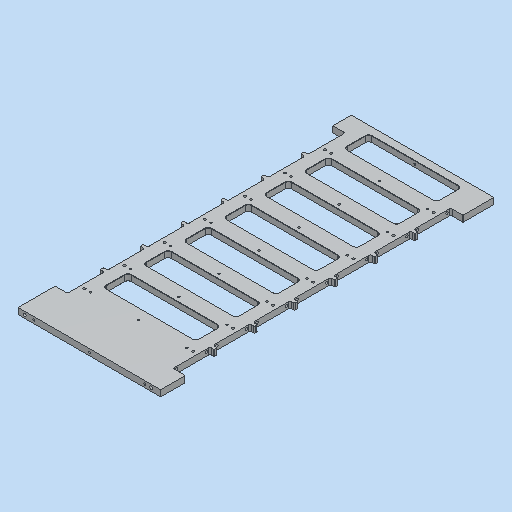
# Autodesk Inventor part: MM0948AN130_G01_114
Saved by Autodesk Inventor 2023.3 (Build 273359000, 359)
## iProperties
Part Number: MM0948AN130_G01_114
Material: 3.3547 AlMg4,5Mn0,7 - AW 5083
Description: =<RBPARTNOTITLE2>
Document SubType Name: Modeling
Designer: ric7an
Mass: 1734.56 g
Surface Area: 1824.37 cm^2
Volume: 642.429 cm^3
Density: 2.7 g/cm^3
Appearance: Aluminium AnP
Created: 2023-03-23
RBDOCUMENTTYPE: DRF
RBDOCUMENTVERSION: 00
RBDRAWINGMAINSCALE: 1:1
RBDRAWINGMISSINGSPEC: --
RBDRAWINGVOLUME: --
RBGBEDGESIN1: +0,5
RBGBEDGESIN2: +0,2
RBGBEDGESOUT1: -0,3
RBGBEDGESOUT2: -0,1
RBMATERIAL: =<Material>
RBMATMEETS: --
RBMATNO: =<Part Number>
RBPARTMADEOF: 10 x 540 x 276 (FM)
RBPARTNO: SIEHE MNR
RBPARTNOTITLE1: manufactured part
RBPARTNOTITLE2: Anfertigungsteil
RBPARTSAFETYINDICATOR: --
RBSURFACE: anodised colourless
RBSURFACE2: eloxiert farblos
RBZEDGESNORM: ISO13715:2002-06
RBZGENDIMCLASS: m
RBZGENDIMNORM: ISO 2768-1:1989-11
RBZGENGEOCLASS: H
RBZGENGEONORM: ISO 2768-2:1989-11
RBZSURFACENORM: ISO13D2:2002-02
RBZTOLERANCENORM: ISO 14405-1:2010-12
AnP_Material: =<Material>
AnP_TemplVers: 20190222
AnP_Kategorie: 1
MaxAbmaße: 10 x 540 x 276 (FM)
AnP_Kommentar_aktuell: =<Comments>
AnP_Material_aktuell: =<Material>
Author: FH/Wi
Keywords: =<RBPARTMADEOF>
Comments: =<RBSURFACE2>
Revision Number: 01
Autodesk Inventor part; units mm, degrees
ref_plane "YZ Plane" through (0, 0, 0) normal (1, 0, 0) x (0, 1, 0)
ref_plane "XZ Plane" through (0, 0, 0) normal (0, 1, 0) x (-1, 0, 0)
sketch "Skizze1" plane through (0, 0, 0) normal (0, 0, 1) x (1, 0, 0)
  line L0 (0, 0) -> (231, 0)
  line L1 (231, 0) -> (231, 540)
  line L2 (231, 540) -> (0, 540)
  line L3 (0, 540) -> (0, 0)
  line L4 (0, 648) -> (0, -108) projected
  line L5 (-46.2, 0) -> (277.2, 0) projected
  point P0 (0, 0)
  dimension "d0" = 540
  dimension "d1" = 231
  constraints: 8 end point, 2 collinear, 2 parallel, 1 horizontal, 1 perpendicular
  measures "d0" distance of L0.end L1.end
  measures "d1" distance of L1.end L2.end
extrude "Extrusion1" add sketch "Skizze1" against normal blind 10
ref_plane "Arbeitsebene1" through (0, 40, -2.5) normal (0, 0, 1) x (1, 0, 0)
sketch "Skizze4" plane through (0, 40, 0) normal (0, 0, 1) x (1, 0, 0)
  line L0 (231, 500) -> (0, 500) projected
  line L1 (0, -40) -> (231, -40) projected
  line L2 (231, -40) -> (231, 500) projected
  point P0 (37.5, 430)
  point P1 (203.5, 430)
  point P2 (193.5, 430)
  point P3 (115.5, 430)
  point P4 (27.5, 430)
  point P5 (115.5, 500)
  dimension "d18" = 78
  dimension "d20" = 10
  dimension "d42" = 10
  dimension "d43" = 156
  dimension "d69" = 470
  dimension "d201" = 27.5
  constraints: 4 horizontal alignment, 1 midpoint, 1 vertical alignment
  measures "d18" distance of point (115.5, 430) point (37.5, 430)
  measures "d20" distance of point (203.5, 430) point (193.5, 430)
  measures "d42" distance of point (37.5, 430) point (27.5, 430)
  measures "d43" distance of point (193.5, 430) point (37.5, 430)
  measures "d69" distance from line of L1 point (27.5, 430)
  measures "d201" distance from line of L2 point (203.5, 430)
hole "Bohrung1" at (37.5, 470, 0) at (193.5, 470, 0) at (115.5, 470, 0) direction (0, 0, -1) diameter 3.242 end through all thread size "M4x0.7" designation "M4" class "6H" standard "ISO Metric profile"
hole "Bohrung2" at (203.5, 470, 0) at (27.5, 470, 0) direction (0, 0, -1) diameter 4 end through all
sketch "Skizze7" plane through (0, 0, 0) normal (0, 0, 1) x (1, 0, 0)
  line L0 (40.5, 527.5) -> (190.5, 527.5)
  line L1 (190.5, 527.5) -> (190.5, 487.5)
  line L2 (190.5, 487.5) -> (40.5, 487.5)
  line L3 (40.5, 487.5) -> (40.5, 527.5)
  line L4 (-48.6, 0) -> (291.6, 0) projected
  line L5 (231, 540) -> (0, 540) projected
  line L6 (40.5, 507.5) -> (190.5, 507.5) construction
  circle A0 centre (203.5, 470) radius 2 projected
  point P0 (0, 0)
  point P1 (115.5, 527.5)
  point P2 (115.5, 540)
  dimension "d60" = 150
  dimension "d61" = 40
  dimension "d163" = 17.5
  constraints: 10 end point, 4 midpoint, 2 parallel, 1 horizontal, 1 perpendicular, 1 vertical alignment
  measures "d60" distance of L0.start L0.end
  measures "d61" distance of L0.end L1.end
  measures "d163" distance from line of A0.centre L2
extrude "Extrusion6" cut sketch "Skizze7" against normal through all contours L0 L1 L2 L3
fillet "Rundung2" radius 5 4 edges at (40.5, 527.5, -5) (40.5, 487.5, -5) (190.5, 487.5, -5) (190.5, 527.5, -5)
sketch "Skizze8" plane through (0, 0, 0) normal (0, -1, 0) x (1, 0, 0)
  line L0 (231, -10) -> (0, -10) projected
  line L1 (0, 0) -> (0, -10) projected
  line L2 (231, 0) -> (231, -10) projected
  line L3 (25.5, -5) -> (205.5, -5)
  point P0 (115.5, -5)
  dimension "d71" = 5
  dimension "d72" = 180
  dimension "d90" = 231
  dimension "d91" = 25.5
  constraints: 2 end point, 1 horizontal, 1 horizontal alignment, 1 midpoint
  measures "d71" distance from line of L0 L3.start
  measures "d72" distance of L3.end L3.start
  measures "d90" distance between parallel lines of L2 L1
  measures "d91" distance from line of L3.start L1
hole "Bohrung3" at (25.5, 0, -5) at (205.5, 0, -5) at (115.5, 0, -5) direction (0, 1, 0) diameter 3.242 depth 15 tip angle 118 thread size "M4x0.7" designation "M4" class "6H" standard "ISO Metric profile"
sketch "Skizze9" plane through (0, 0, 0) normal (0, -1, 0) x (1, 0, 0)
  circle A0 centre (25.5, -5) radius 1.621 projected
  circle A1 centre (205.5, -5) radius 1.621 projected
  point P0 (0, 0)
  point P1 (10.5, -5)
  point P2 (215.5, -5)
  dimension "d92" = 15
  dimension "d187" = 10
  constraints: 2 horizontal alignment
  measures "d92" distance of A0.centre point (10.5, -5)
  measures "d187" distance of point (215.5, -5) A1.centre
hole "Bohrung4" at (10.5, 0, -5) at (215.5, 0, -5) direction (0, 1, 0) diameter 5 depth 10 tip angle 118
sketch "Skizze10" plane through (0, 540, 0) normal (0, 1, 0) x (1, 0, 0)
  line L0 (231, 0) -> (0, 0) projected
  line L1 (231, 0) -> (231, 10) projected
  line L2 (0, 0) -> (0, 10) projected
  line L3 (15.5, 5) -> (215.5, 5)
  point P0 (115.5, 5)
  dimension "d93" = 5
  dimension "d94" = 200
  dimension "d95" = 231
  dimension "d96" = 15.5
  constraints: 2 end point, 1 horizontal, 1 horizontal alignment, 1 midpoint
  measures "d93" distance from line of L0 L3.start
  measures "d94" distance of L3.end L3.start
  measures "d95" distance between parallel lines of L1 L2
  measures "d96" distance from line of L3.start L2
hole "Bohrung5" at (15.5, 540, -5) at (215.5, 540, -5) at (115.5, 540, -5) direction (0, -1, 0) diameter 3.242 depth 15 tip angle 118 thread size "M4x0.7" designation "M4" class "6H" standard "ISO Metric profile"
chamfer "Fase1" distance 0.5 angle 45 16 edges at (40.5, 507.5, -10) (41.9645, 488.9645, -10) (115.5, 487.5, -10) (189.0355, 488.9645, -10) (190.5, 507.5, -10) (189.0355, 526.0355, -10) (115.5, 527.5, -10) (41.9645, 526.0355, -10) (40.5, 507.5, 0) (41.9645, 526.0355, 0) (115.5, 527.5, 0) (189.0355, 526.0355, 0) (190.5, 507.5, 0) (189.0355, 488.9645, 0) (115.5, 487.5, 0) (41.9645, 488.9645, 0)
sketch "Skizze11" plane through (0, 540, 0) normal (0, 1, 0) x (1, 0, 0)
  circle A0 centre (15.5, 5) radius 1.621 projected
  circle A1 centre (215.5, 5) radius 1.621 projected
  point P0 (0, 0)
  point P1 (200.5, 5)
  dimension "d107" = 200
  dimension "d200" = 15
  constraints: 1 horizontal alignment
  measures "d107" distance of A1.centre A0.centre
  measures "d200" distance of A1.centre point (200.5, 5)
hole "Bohrung6" at (200.5, 540, -5) direction (0, -1, 0) diameter 5 depth 10 tip angle 118
sketch "Skizze16" plane through (0, 0, -10) normal (0, 0, -1) x (-1, 0, 0)
  line L0 (0, 0) -> (0, 540) projected
  line L1 (0, 540) -> (-231, 540) projected
  line L2 (0, 510) -> (-20, 510)
  line L3 (-20, 510) -> (-20, 450)
  line L4 (-20, 450) -> (0, 450)
  line L5 (0, 450) -> (0, 510)
  line L6 (-231, 540) -> (-231, 0) projected
  line L7 (-231, 490) -> (-211, 490)
  line L8 (-211, 490) -> (-211, 430)
  line L9 (-211, 430) -> (-231, 430)
  line L10 (-231, 430) -> (-231, 490)
  circle A0 centre (-27.5, 470) radius 2 projected
  circle A1 centre (-203.5, 470) radius 2 projected
  point P0 (0, 450)
  dimension "d148" = 60
  dimension "d149" = 20
  dimension "d150" = 20
  dimension "d164" = 40
  dimension "d165" = 20
  constraints: 16 end point, 5 parallel, 2 horizontal, 2 perpendicular, 2 point on line
  measures "d148" distance of L2.end L3.end
  measures "d149" distance of L3.end L4.end
  measures "d150" distance of L7.start L7.end
  measures "d164" distance from line of L2 A0.centre
  measures "d165" distance from line of A1.centre L7
extrude "Extrusion8" cut sketch "Skizze16" against normal through all contours L4 L3 L2 L0 | L7 L8 L9 L6
sketch "Skizze18" plane through (20, 450, -10) normal (-1, 0, 0) x (0, 0, 1)
  line L0 (10, 60) -> (10, 0) projected
  line L1 (0, 60) -> (10, 60) projected
  line L2 (10, 30) -> (5, 30)
  line L3 (0, 0) -> (0, 60) projected
  point P0 (10, -450)
  point P1 (6, 54)
  point P2 (6, 6)
  dimension "d174" = 6
  dimension "d175" = 6
  constraints: 2 end point, 1 horizontal, 1 midpoint, 1 symmetric about line
  measures "d174" distance from line of point (6, 54) L1
  measures "d175" distance from line of point (6, 54) L3
hole "Bohrung11" at (20, 504, -4) at (20, 456, -4) direction (1, 0, 0) diameter 4.134 depth 14.2 tip angle 118 thread size "M5x0.8" designation "M5" class "6H" standard "ISO Metric profile"
sketch "Skizze20" plane through (211, 430, 1) normal (1, 0, 0) x (0, 0, -1)
  line L0 (10, 30) -> (1, 30)
  line L1 (1, 0) -> (1, 60) projected
  line L2 (1, 60) -> (11, 60) projected
  line L3 (11, 60) -> (11, 0) projected
  point P0 (10, -450)
  point P1 (5, 54)
  point P2 (5, 6)
  dimension "d198" = 6
  dimension "d199" = 6
  constraints: 2 end point, 1 horizontal, 1 midpoint, 1 symmetric about line
  measures "d198" distance from line of point (5, 54) L2
  measures "d199" distance from line of L3 point (5, 54)
hole "Bohrung13" at (211, 484, -4) at (211, 436, -4) direction (-1, 0, 0) diameter 4.134 depth 14.2 tip angle 118
fillet "Rundung4" radius 2.5 4 edges at (20, 450, -5) (20, 510, -5) (211, 490, -5) (211, 430, -5)
pattern_linear "Rechteckige Anordnung2" count 7 spacing 65 along (0, -1, 0) of "Bohrung2", "Bohrung1", "Extrusion8", "Rundung2", "Fase1", "Extrusion6", "Bohrung13", "Bohrung11", "Rundung4"
sketch "Skizze21" plane through (0, 0, 0) normal (0, 0, 1) x (1, 0, 0)
  line L0 (40, 132.5) -> (40, 102.5) projected
  arc A0 (45.5, 138) -> (40, 132.5) centre (45.5, 132.5) ccw projected
  line L1 (185.5, 138) -> (45.5, 138) projected
  arc A1 (191, 132.5) -> (185.5, 138) centre (185.5, 132.5) ccw projected
  line L2 (191, 102.5) -> (191, 132.5) projected
  arc A2 (185.5, 97) -> (191, 102.5) centre (185.5, 102.5) ccw projected
  line L3 (45.5, 97) -> (185.5, 97) projected
  arc A3 (40, 102.5) -> (45.5, 97) centre (45.5, 102.5) ccw projected
  line L4 (40, 262.5) -> (40, 232.5) projected
  arc A4 (45.5, 268) -> (40, 262.5) centre (45.5, 262.5) ccw projected
  line L5 (185.5, 268) -> (45.5, 268) projected
  arc A5 (191, 262.5) -> (185.5, 268) centre (185.5, 262.5) ccw projected
  line L6 (191, 232.5) -> (191, 262.5) projected
  arc A6 (185.5, 227) -> (191, 232.5) centre (185.5, 232.5) ccw projected
  line L7 (45.5, 227) -> (185.5, 227) projected
  arc A7 (40, 232.5) -> (45.5, 227) centre (45.5, 232.5) ccw projected
  line L8 (40, 392.5) -> (40, 362.5) projected
  arc A8 (45.5, 398) -> (40, 392.5) centre (45.5, 392.5) ccw projected
  line L9 (185.5, 398) -> (45.5, 398) projected
  arc A9 (191, 392.5) -> (185.5, 398) centre (185.5, 392.5) ccw projected
  line L10 (191, 362.5) -> (191, 392.5) projected
  arc A10 (185.5, 357) -> (191, 362.5) centre (185.5, 362.5) ccw projected
  line L11 (45.5, 357) -> (185.5, 357) projected
  arc A11 (40, 362.5) -> (45.5, 357) centre (45.5, 362.5) ccw projected
  line L12 (231, 40) -> (213.5, 40) projected
  arc A12 (211, 42.5) -> (213.5, 40) centre (213.5, 42.5) ccw projected
  line L13 (211, 42.5) -> (211, 97.5) projected
  arc A13 (213.5, 100) -> (211, 97.5) centre (213.5, 97.5) ccw projected
  line L14 (213.5, 100) -> (231, 100) projected
  line L15 (231, 100) -> (231, 105) projected
  line L16 (231, 105) -> (213.5, 105) projected
  arc A14 (211, 107.5) -> (213.5, 105) centre (213.5, 107.5) ccw projected
  line L17 (211, 107.5) -> (211, 162.5) projected
  arc A15 (213.5, 165) -> (211, 162.5) centre (213.5, 162.5) ccw projected
  line L18 (213.5, 165) -> (231, 165) projected
  line L19 (231, 165) -> (231, 170) projected
  line L20 (231, 170) -> (213.5, 170) projected
  arc A16 (211, 172.5) -> (213.5, 170) centre (213.5, 172.5) ccw projected
  line L21 (211, 172.5) -> (211, 227.5) projected
  arc A17 (213.5, 230) -> (211, 227.5) centre (213.5, 227.5) ccw projected
  line L22 (213.5, 230) -> (231, 230) projected
  line L23 (231, 230) -> (231, 235) projected
  line L24 (231, 235) -> (213.5, 235) projected
  arc A18 (211, 237.5) -> (213.5, 235) centre (213.5, 237.5) ccw projected
  line L25 (211, 237.5) -> (211, 292.5) projected
  arc A19 (213.5, 295) -> (211, 292.5) centre (213.5, 292.5) ccw projected
  line L26 (213.5, 295) -> (231, 295) projected
  line L27 (231, 295) -> (231, 300) projected
  line L28 (231, 300) -> (213.5, 300) projected
  arc A20 (211, 302.5) -> (213.5, 300) centre (213.5, 302.5) ccw projected
  line L29 (211, 302.5) -> (211, 357.5) projected
  arc A21 (213.5, 360) -> (211, 357.5) centre (213.5, 357.5) ccw projected
  line L30 (213.5, 360) -> (231, 360) projected
  line L31 (231, 360) -> (231, 365) projected
  line L32 (231, 365) -> (213.5, 365) projected
  arc A22 (211, 367.5) -> (213.5, 365) centre (213.5, 367.5) ccw projected
  line L33 (211, 367.5) -> (211, 422.5) projected
  arc A23 (213.5, 425) -> (211, 422.5) centre (213.5, 422.5) ccw projected
  line L34 (213.5, 425) -> (231, 425) projected
  line L35 (231, 425) -> (231, 430) projected
  line L36 (231, 430) -> (213.5, 430) projected
  arc A24 (211, 432.5) -> (213.5, 430) centre (213.5, 432.5) ccw projected
  line L37 (211, 432.5) -> (211, 487.5) projected
  arc A25 (213.5, 490) -> (211, 487.5) centre (213.5, 487.5) ccw projected
  line L38 (213.5, 490) -> (231, 490) projected
  line L39 (231, 490) -> (231, 540) projected
  line L40 (231, 540) -> (0, 540) projected
  line L41 (0, 540) -> (0, 510) projected
  line L42 (0, 510) -> (17.5, 510) projected
  arc A26 (20, 507.5) -> (17.5, 510) centre (17.5, 507.5) ccw projected
  line L43 (20, 507.5) -> (20, 452.5) projected
  arc A27 (17.5, 450) -> (20, 452.5) centre (17.5, 452.5) ccw projected
  line L44 (17.5, 450) -> (0, 450) projected
  line L45 (0, 450) -> (0, 445) projected
  line L46 (0, 445) -> (17.5, 445) projected
  arc A28 (20, 442.5) -> (17.5, 445) centre (17.5, 442.5) ccw projected
  line L47 (20, 442.5) -> (20, 387.5) projected
  arc A29 (17.5, 385) -> (20, 387.5) centre (17.5, 387.5) ccw projected
  line L48 (17.5, 385) -> (0, 385) projected
  line L49 (0, 385) -> (0, 380) projected
  line L50 (0, 380) -> (17.5, 380) projected
  arc A30 (20, 377.5) -> (17.5, 380) centre (17.5, 377.5) ccw projected
  line L51 (20, 377.5) -> (20, 322.5) projected
  arc A31 (17.5, 320) -> (20, 322.5) centre (17.5, 322.5) ccw projected
  line L52 (17.5, 320) -> (0, 320) projected
  line L53 (0, 320) -> (0, 315) projected
  line L54 (0, 315) -> (17.5, 315) projected
  arc A32 (20, 312.5) -> (17.5, 315) centre (17.5, 312.5) ccw projected
  line L55 (20, 312.5) -> (20, 257.5) projected
  arc A33 (17.5, 255) -> (20, 257.5) centre (17.5, 257.5) ccw projected
  line L56 (17.5, 255) -> (0, 255) projected
  line L57 (0, 255) -> (0, 250) projected
  line L58 (0, 250) -> (17.5, 250) projected
  arc A34 (20, 247.5) -> (17.5, 250) centre (17.5, 247.5) ccw projected
  line L59 (20, 247.5) -> (20, 192.5) projected
  arc A35 (17.5, 190) -> (20, 192.5) centre (17.5, 192.5) ccw projected
  line L60 (17.5, 190) -> (0, 190) projected
  line L61 (0, 190) -> (0, 185) projected
  line L62 (0, 185) -> (17.5, 185) projected
  arc A36 (20, 182.5) -> (17.5, 185) centre (17.5, 182.5) ccw projected
  line L63 (20, 182.5) -> (20, 127.5) projected
  arc A37 (17.5, 125) -> (20, 127.5) centre (17.5, 127.5) ccw projected
  line L64 (17.5, 125) -> (0, 125) projected
  line L65 (0, 125) -> (0, 120) projected
  line L66 (0, 120) -> (17.5, 120) projected
  arc A38 (20, 117.5) -> (17.5, 120) centre (17.5, 117.5) ccw projected
  line L67 (20, 117.5) -> (20, 62.5) projected
  arc A39 (17.5, 60) -> (20, 62.5) centre (17.5, 62.5) ccw projected
  line L68 (17.5, 60) -> (0, 60) projected
  line L69 (0, 60) -> (0, 0) projected
  line L70 (0, 0) -> (231, 0) projected
  line L71 (231, 0) -> (231, 40) projected
  circle A40 centre (115.5, 470) radius 1.621 projected
  circle A41 centre (37.5, 470) radius 1.621 projected
  circle A42 centre (193.5, 470) radius 1.621 projected
  circle A43 centre (27.5, 470) radius 2 projected
  circle A44 centre (203.5, 470) radius 2 projected
  line L72 (40, 522.5) -> (40, 492.5) projected
  arc A45 (45.5, 528) -> (40, 522.5) centre (45.5, 522.5) ccw projected
  line L73 (185.5, 528) -> (45.5, 528) projected
  arc A46 (191, 522.5) -> (185.5, 528) centre (185.5, 522.5) ccw projected
  line L74 (191, 492.5) -> (191, 522.5) projected
  arc A47 (185.5, 487) -> (191, 492.5) centre (185.5, 492.5) ccw projected
  line L75 (45.5, 487) -> (185.5, 487) projected
  arc A48 (40, 492.5) -> (45.5, 487) centre (45.5, 492.5) ccw projected
  circle A49 centre (37.5, 405) radius 1.621 projected
  circle A50 centre (115.5, 405) radius 1.621 projected
  circle A51 centre (193.5, 405) radius 1.621 projected
  circle A52 centre (27.5, 405) radius 2 projected
  circle A53 centre (203.5, 405) radius 2 projected
  circle A54 centre (37.5, 340) radius 1.621 projected
  circle A55 centre (115.5, 340) radius 1.621 projected
  circle A56 centre (193.5, 340) radius 1.621 projected
  circle A57 centre (27.5, 340) radius 2 projected
  circle A58 centre (203.5, 340) radius 2 projected
  circle A59 centre (37.5, 275) radius 1.621 projected
  circle A60 centre (115.5, 275) radius 1.621 projected
  circle A61 centre (193.5, 275) radius 1.621 projected
  circle A62 centre (27.5, 275) radius 2 projected
  circle A63 centre (203.5, 275) radius 2 projected
  circle A64 centre (37.5, 210) radius 1.621 projected
  circle A65 centre (115.5, 210) radius 1.621 projected
  circle A66 centre (193.5, 210) radius 1.621 projected
  circle A67 centre (27.5, 210) radius 2 projected
  circle A68 centre (203.5, 210) radius 2 projected
  circle A69 centre (37.5, 145) radius 1.621 projected
  circle A70 centre (115.5, 145) radius 1.621 projected
  circle A71 centre (193.5, 145) radius 1.621 projected
  circle A72 centre (27.5, 145) radius 2 projected
  circle A73 centre (203.5, 145) radius 2 projected
  circle A74 centre (37.5, 80) radius 1.621 projected
  circle A75 centre (115.5, 80) radius 1.621 projected
  circle A76 centre (193.5, 80) radius 1.621 projected
  circle A77 centre (27.5, 80) radius 2 projected
  circle A78 centre (203.5, 80) radius 2 projected
  line L76 (40, 457.5) -> (40, 427.5) projected
  arc A79 (45.5, 463) -> (40, 457.5) centre (45.5, 457.5) ccw projected
  line L77 (185.5, 463) -> (45.5, 463) projected
  arc A80 (191, 457.5) -> (185.5, 463) centre (185.5, 457.5) ccw projected
  line L78 (191, 427.5) -> (191, 457.5) projected
  arc A81 (185.5, 422) -> (191, 427.5) centre (185.5, 427.5) ccw projected
  line L79 (45.5, 422) -> (185.5, 422) projected
  arc A82 (40, 427.5) -> (45.5, 422) centre (45.5, 427.5) ccw projected
  line L80 (40, 327.5) -> (40, 297.5) projected
  arc A83 (45.5, 333) -> (40, 327.5) centre (45.5, 327.5) ccw projected
  line L81 (185.5, 333) -> (45.5, 333) projected
  arc A84 (191, 327.5) -> (185.5, 333) centre (185.5, 327.5) ccw projected
  line L82 (191, 297.5) -> (191, 327.5) projected
  arc A85 (185.5, 292) -> (191, 297.5) centre (185.5, 297.5) ccw projected
  line L83 (45.5, 292) -> (185.5, 292) projected
  arc A86 (40, 297.5) -> (45.5, 292) centre (45.5, 297.5) ccw projected
  line L84 (40, 197.5) -> (40, 167.5) projected
  arc A87 (45.5, 203) -> (40, 197.5) centre (45.5, 197.5) ccw projected
  line L85 (185.5, 203) -> (45.5, 203) projected
  arc A88 (191, 197.5) -> (185.5, 203) centre (185.5, 197.5) ccw projected
  line L86 (191, 167.5) -> (191, 197.5) projected
  arc A89 (185.5, 162) -> (191, 167.5) centre (185.5, 167.5) ccw projected
  line L87 (45.5, 162) -> (185.5, 162) projected
  arc A90 (40, 167.5) -> (45.5, 162) centre (45.5, 167.5) ccw projected
  line L88 (0, 450) -> (13, 450)
  line L89 (13, 450) -> (13, 445)
  line L90 (13, 445) -> (0, 445)
  line L91 (0, 445) -> (0, 450)
  line L92 (231, 430) -> (218, 430)
  line L93 (218, 430) -> (218, 425)
  line L94 (218, 425) -> (231, 425)
  line L95 (231, 425) -> (231, 430)
  point P0 (0, 0)
  dimension "d204" = 7
  dimension "d205" = 7
  constraints: 16 end point, 4 parallel, 2 horizontal, 2 perpendicular, 2 point on line
  measures "d204" distance between parallel lines of L37 L93
  measures "d205" distance between parallel lines of L43 L89
extrude "Extrusion9" cut sketch "Skizze21" against normal through all contours L93 L36 L35 L34 | L46 L45 L44 L89
pattern_linear "Rechteckige Anordnung5" count 6 spacing 65 along (0, -1, 0) of "Extrusion9"
fillet "Rundung5" radius 1 27 edges at (13, 450, -5) (13, 445, -5) (13, 385, -5) (13, 380, -5) (13, 320, -5) (13, 315, -5) (13, 255, -5) (13, 250, -5) (13, 190, -5) (13, 185, -5) (13, 125, -5) (13, 120, -5) (0, 60, -5) (231, 40, -5) (218, 100, -5) (218, 105, -5) (218, 165, -5) (218, 170, -5) (218, 230, -5) (218, 235, -5) (218, 295, -5) (218, 300, -5) (218, 365, -5) (218, 360, -5) (218, 430, -5) (218, 425, -5) (231, 490, -5)
equation "\"d18\" = 0.5 * d43"
equation "\"d91\" = -0.5 * d72 + 0.5 * d90"
equation "\"d96\" = -0.5 * d94 + 0.5 * d95"
equation "\"d150\" = d149"
